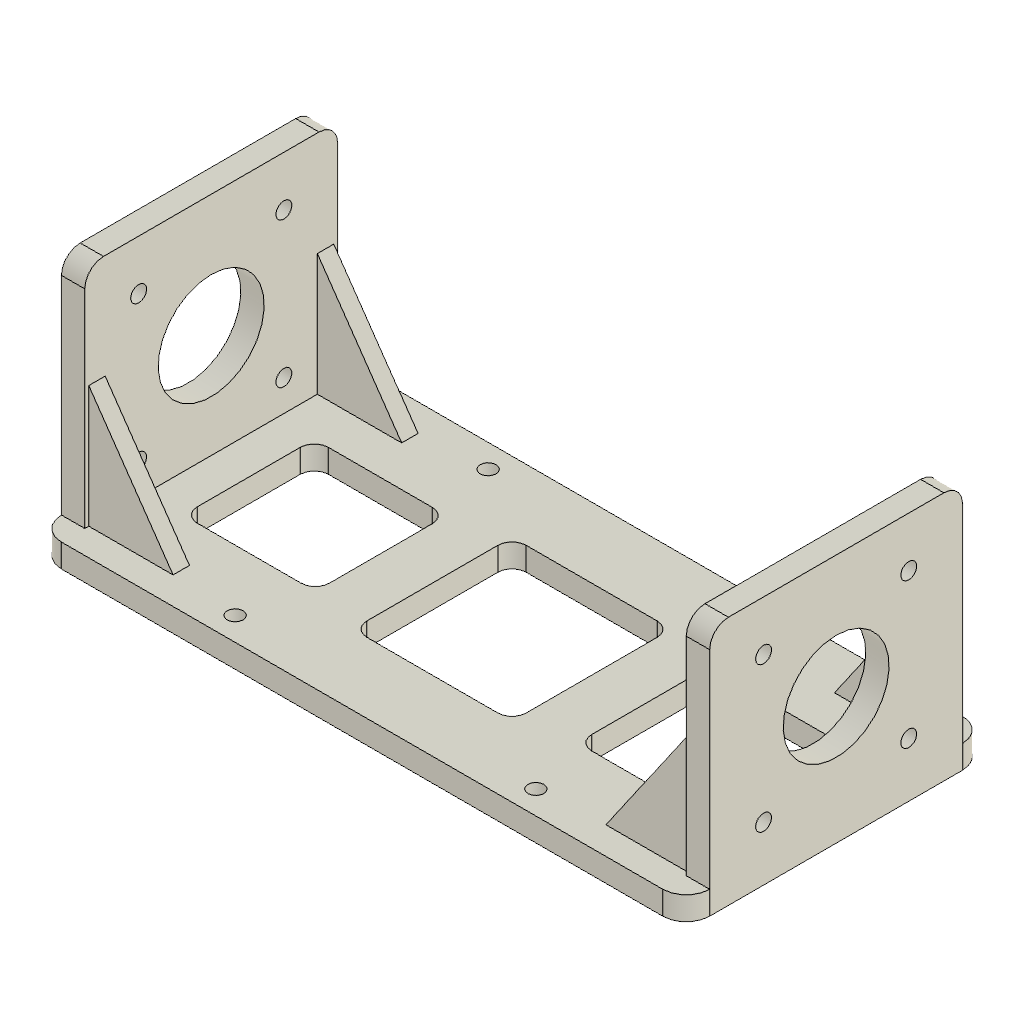
Base_NEMA17_AS5600 (Autodesk Fusion 360 design; units mm, degrees)
description: Soporte doble NEMA17 con encoders AS5600. Ejes coaxiales hacia afuera; canal abierto central. Dimensiones nominales de fijacion por confirmar.
description: Envolvente de motor + AS5600: 42.3 mm nominal y 44.2 mm confirmados. Subdivisiones, ejes, tapas y distribucion de pines son representativos.
Autodesk Fusion 360 part; units mm, degrees
sketch "Boceto1" plane through (0, 0, 0) normal (0, 0, 1) x (1, 0, 0) in component "01 Base imprimible"
  line L0 (-69.2, -32) -> (69.2, -32)
  line L1 (69.2, -32) -> (69.2, 32)
  line L2 (69.2, 32) -> (-69.2, 32)
  line L3 (-69.2, 32) -> (-69.2, -32)
  dimension "d30" = 69.2
  dimension "d31" = 32
  dimension "d32" = 138.4
  dimension "d33" = 64
  constraint horizontal L0
  constraint vertical L1
  constraint horizontal L2
  constraint vertical L3
  measures "d30" horizontal distance of origin L0.start
  measures "d31" vertical distance of origin L0.start
  measures "d32" horizontal distance of L0.start L0.end
  measures "d33" vertical distance of L0.end L1.end
extrude "01 Plataforma de 5 mm" add sketch "Boceto1" along normal blind 5 makes body 1 in component "01 Base imprimible"
fillet "02 Esquinas de plataforma R5" radius 5 4 edges at (-69.2, 32, 2.5) (69.2, 32, 2.5) (69.2, -32, 2.5) (-69.2, -32, 2.5) on bodies 1 in component "01 Base imprimible"
ref_plane "PlanoDeObra1" through (64.2, 0, 0) normal (1, 0, 0) x (0, 1, 0) in component "01 Base imprimible"
sketch "Boceto2" plane through (64.2, 0, 0) normal (1, 0, 0) x (0, 0, -1) in component "01 Base imprimible"
  line L0 (-53.3, -27) -> (-5, -27)
  line L1 (-5, -27) -> (-5, 27)
  line L2 (-5, 27) -> (-53.3, 27)
  line L3 (-53.3, 27) -> (-53.3, -27)
  dimension "d41" = 27
  dimension "d43" = 54
  constraint horizontal L0
  constraint vertical L1
  constraint horizontal L2
  constraint vertical L3
  measures "d41" vertical distance of origin L0.start
  measures "d43" vertical distance of L0.end L1.end
extrude "Placa de fijacion derecho" add sketch "Boceto2" along normal blind 5 bodies 1 in component "01 Base imprimible"
ref_plane "PlanoDeObra2" through (-64.2, 0, 0) normal (1, 0, 0) x (0, 1, 0) in component "01 Base imprimible"
sketch "Boceto3" plane through (-64.2, 0, 0) normal (1, 0, 0) x (0, 0, -1) in component "01 Base imprimible"
  line L0 (-53.3, -27) -> (-5, -27)
  line L1 (-5, -27) -> (-5, 27)
  line L2 (-5, 27) -> (-53.3, 27)
  line L3 (-53.3, 27) -> (-53.3, -27)
  dimension "d49" = 27
  dimension "d51" = 54
  constraint horizontal L0
  constraint vertical L1
  constraint horizontal L2
  constraint vertical L3
  measures "d49" vertical distance of origin L0.start
  measures "d51" vertical distance of L0.end L1.end
extrude "Placa de fijacion izquierdo" add sketch "Boceto3" against normal blind 5 bodies 1 in component "01 Base imprimible"
fillet "Esquinas superiores R4" radius 4 4 edges at (-66.7, -27, 53.3) (-66.7, 27, 53.3) (66.7, 27, 53.3) (66.7, -27, 53.3) on bodies 1 in component "01 Base imprimible"
ref_plane "PlanoDeObra3" through (64.2, 0, 0) normal (1, 0, 0) x (0, 1, 0) in component "01 Base imprimible"
sketch "Boceto4" plane through (64.2, 0, 0) normal (1, 0, 0) x (0, 0, -1) in component "01 Base imprimible"
  circle A0 centre (-27.15, 0) radius 11.3
  line L0 (0, 0) -> (-27.15, 0) construction
  circle A1 centre (-11.65, -15.5) radius 1.7
  circle A2 centre (-42.65, -15.5) radius 1.7
  circle A3 centre (-11.65, 15.5) radius 1.7
  circle A4 centre (-42.65, 15.5) radius 1.7
  dimension "d59" = 22.6
  dimension "d60" = 11.65
  dimension "d61" = 15.5
  dimension "d62" = 3.4
  dimension "d63" = 42.65
  dimension "d64" = 15.5
  dimension "d65" = 3.4
  dimension "d66" = 11.65
  dimension "d67" = 15.5
  dimension "d68" = 3.4
  dimension "d69" = 42.65
  dimension "d70" = 15.5
  dimension "d71" = 3.4
  constraint horizontal L0
  measures "d59" diameter of A0
  measures "d60" horizontal distance of L0.start A1.centre
  measures "d61" vertical distance of L0.start A1.centre
  measures "d62" diameter of A1
  measures "d63" horizontal distance of L0.start A2.centre
  measures "d64" vertical distance of L0.start A2.centre
  measures "d65" diameter of A2
  measures "d66" horizontal distance of L0.start A3.centre
  measures "d67" vertical distance of L0.start A3.centre
  measures "d68" diameter of A3
  measures "d69" horizontal distance of L0.start A4.centre
  measures "d70" vertical distance of L0.start A4.centre
  measures "d71" diameter of A4
extrude "Centrador y cuatro M3 derecho" cut sketch "Boceto4" along normal blind 5 bodies 1 in component "01 Base imprimible"
ref_plane "PlanoDeObra4" through (-64.2, 0, 0) normal (1, 0, 0) x (0, 1, 0) in component "01 Base imprimible"
sketch "Boceto5" plane through (-64.2, 0, 0) normal (1, 0, 0) x (0, 0, -1) in component "01 Base imprimible"
  circle A0 centre (-27.15, 0) radius 11.3
  line L0 (0, 0) -> (-27.15, 0) construction
  circle A1 centre (-11.65, -15.5) radius 1.7
  circle A2 centre (-42.65, -15.5) radius 1.7
  circle A3 centre (-11.65, 15.5) radius 1.7
  circle A4 centre (-42.65, 15.5) radius 1.7
  dimension "d77" = 22.6
  dimension "d78" = 11.65
  dimension "d79" = 15.5
  dimension "d80" = 3.4
  dimension "d81" = 42.65
  dimension "d82" = 15.5
  dimension "d83" = 3.4
  dimension "d84" = 11.65
  dimension "d85" = 15.5
  dimension "d86" = 3.4
  dimension "d87" = 42.65
  dimension "d88" = 15.5
  dimension "d89" = 3.4
  constraint horizontal L0
  measures "d77" diameter of A0
  measures "d78" horizontal distance of L0.start A1.centre
  measures "d79" vertical distance of L0.start A1.centre
  measures "d80" diameter of A1
  measures "d81" horizontal distance of L0.start A2.centre
  measures "d82" vertical distance of L0.start A2.centre
  measures "d83" diameter of A2
  measures "d84" horizontal distance of L0.start A3.centre
  measures "d85" vertical distance of L0.start A3.centre
  measures "d86" diameter of A3
  measures "d87" horizontal distance of L0.start A4.centre
  measures "d88" vertical distance of L0.start A4.centre
  measures "d89" diameter of A4
extrude "Centrador y cuatro M3 izquierdo" cut sketch "Boceto5" against normal blind 5 bodies 1 in component "01 Base imprimible"
ref_plane "PlanoDeObra5" through (0, 22.65, 0) normal (0, 1, 0) x (0, 0, 1) in component "01 Base imprimible"
sketch "Boceto6" plane through (0, 22.65, 0) normal (0, 1, 0) x (1, 0, 0) in component "01 Base imprimible"
  line L0 (-64.2, -5) -> (-46.2, -5)
  line L1 (-46.2, -5) -> (-64.2, -31)
  line L2 (-64.2, -31) -> (-64.2, -5)
  dimension "d94" = 64.2
  dimension "d96" = 18
  dimension "d97" = 26
  constraint horizontal L0
  constraint vertical L2
  measures "d94" horizontal distance of origin L0.start
  measures "d96" horizontal distance of L0.start L0.end
  measures "d97" vertical distance of L0.start L1.end
extrude "Refuerzo triangular -1 -1" add sketch "Boceto6" along normal blind 3.5 bodies 1 in component "01 Base imprimible"
sketch "Boceto7" plane through (0, 22.65, 0) normal (0, 1, 0) x (1, 0, 0) in component "01 Base imprimible"
  line L0 (64.2, -5) -> (46.2, -5)
  line L1 (46.2, -5) -> (64.2, -31)
  line L2 (64.2, -31) -> (64.2, -5)
  dimension "d100" = 64.2
  dimension "d102" = 18
  dimension "d103" = 26
  constraint horizontal L0
  constraint vertical L2
  measures "d100" horizontal distance of origin L0.start
  measures "d102" horizontal distance of L0.start L0.end
  measures "d103" vertical distance of L0.start L1.end
extrude "Refuerzo triangular 1 -1" add sketch "Boceto7" along normal blind 3.5 bodies 1 in component "01 Base imprimible"
ref_plane "PlanoDeObra6" through (0, -22.65, 0) normal (0, 1, 0) x (0, 0, 1) in component "01 Base imprimible"
sketch "Boceto8" plane through (0, -22.65, 0) normal (0, 1, 0) x (1, 0, 0) in component "01 Base imprimible"
  line L0 (-64.2, -5) -> (-46.2, -5)
  line L1 (-46.2, -5) -> (-64.2, -31)
  line L2 (-64.2, -31) -> (-64.2, -5)
  dimension "d108" = 64.2
  dimension "d110" = 18
  dimension "d111" = 26
  constraint horizontal L0
  constraint vertical L2
  measures "d108" horizontal distance of origin L0.start
  measures "d110" horizontal distance of L0.start L0.end
  measures "d111" vertical distance of L0.start L1.end
extrude "Refuerzo triangular -1 1" add sketch "Boceto8" against normal blind 3.5 bodies 1 in component "01 Base imprimible"
sketch "Boceto9" plane through (0, -22.65, 0) normal (0, 1, 0) x (1, 0, 0) in component "01 Base imprimible"
  line L0 (64.2, -5) -> (46.2, -5)
  line L1 (46.2, -5) -> (64.2, -31)
  line L2 (64.2, -31) -> (64.2, -5)
  dimension "d114" = 64.2
  dimension "d116" = 18
  dimension "d117" = 26
  constraint horizontal L0
  constraint vertical L2
  measures "d114" horizontal distance of origin L0.start
  measures "d116" horizontal distance of L0.start L0.end
  measures "d117" vertical distance of L0.start L1.end
extrude "Refuerzo triangular 1 1" add sketch "Boceto9" against normal blind 3.5 bodies 1 in component "01 Base imprimible"
sketch "Boceto10" plane through (0, 0, 0) normal (0, 0, 1) x (1, 0, 0) in component "01 Base imprimible"
  line L0 (-17, -17) -> (17, -17)
  line L1 (17, -17) -> (17, 17)
  line L2 (17, 17) -> (-17, 17)
  line L3 (-17, 17) -> (-17, -17)
  line L4 (-56.2, -14) -> (-28, -14)
  line L5 (-28, -14) -> (-28, 14)
  line L6 (-28, 14) -> (-56.2, 14)
  line L7 (-56.2, 14) -> (-56.2, -14)
  line L8 (28, -14) -> (56.2, -14)
  line L9 (56.2, -14) -> (56.2, 14)
  line L10 (56.2, 14) -> (28, 14)
  line L11 (28, 14) -> (28, -14)
  dimension "d120" = 17
  dimension "d121" = 17
  dimension "d122" = 34
  dimension "d123" = 34
  dimension "d124" = 56.2
  dimension "d125" = 14
  dimension "d126" = 28.2
  dimension "d127" = 28
  dimension "d128" = 28
  dimension "d129" = 14
  dimension "d130" = 28.2
  dimension "d131" = 28
  constraint horizontal L0
  constraint vertical L1
  constraint horizontal L2
  constraint vertical L3
  constraint horizontal L4
  constraint vertical L5
  constraint horizontal L6
  constraint vertical L7
  constraint horizontal L8
  constraint vertical L9
  constraint horizontal L10
  constraint vertical L11
  measures "d120" horizontal distance of origin L0.start
  measures "d121" vertical distance of origin L0.start
  measures "d122" horizontal distance of L0.start L0.end
  measures "d123" vertical distance of L0.end L1.end
  measures "d124" horizontal distance of origin L4.start
  measures "d125" vertical distance of origin L4.start
  measures "d126" horizontal distance of L4.start L4.end
  measures "d127" vertical distance of L4.end L5.end
  measures "d128" horizontal distance of origin L8.start
  measures "d129" vertical distance of origin L8.start
  measures "d130" horizontal distance of L8.start L8.end
  measures "d131" vertical distance of L8.end L9.end
extrude "Tres ventanas inferiores" cut sketch "Boceto10" along normal blind 5 bodies 1 in component "01 Base imprimible"
fillet "Ventanas R3" radius 3 12 edges at (17, 17, 2.5) (-17, 17, 2.5) (17, -17, 2.5) (-17, -17, 2.5) (-28, 14, 2.5) (-56.2, 14, 2.5) (-28, -14, 2.5) (-56.2, -14, 2.5) (56.2, 14, 2.5) (28, 14, 2.5) (56.2, -14, 2.5) (28, -14, 2.5) on bodies 1 in component "01 Base imprimible"
sketch "Boceto11" plane through (0, 0, 0) normal (0, 0, 1) x (1, 0, 0) in component "01 Base imprimible"
  circle A0 centre (-32.1, -27) radius 1.7
  dimension "d136" = 32.1
  dimension "d137" = 27
  dimension "d138" = 3.4
  measures "d136" horizontal distance of origin A0.centre
  measures "d137" vertical distance of origin A0.centre
  measures "d138" diameter of A0
extrude "Anclaje M3 -1 -1" cut sketch "Boceto11" along normal blind 5 bodies 1 in component "01 Base imprimible"
sketch "Boceto12" plane through (0, 0, 0) normal (0, 0, 1) x (1, 0, 0) in component "01 Base imprimible"
  circle A0 centre (-32.1, 27) radius 1.7
  dimension "d141" = 32.1
  dimension "d142" = 27
  dimension "d143" = 3.4
  measures "d141" horizontal distance of origin A0.centre
  measures "d142" vertical distance of origin A0.centre
  measures "d143" diameter of A0
extrude "Anclaje M3 -1 1" cut sketch "Boceto12" along normal blind 5 bodies 1 in component "01 Base imprimible"
sketch "Boceto13" plane through (0, 0, 0) normal (0, 0, 1) x (1, 0, 0) in component "01 Base imprimible"
  circle A0 centre (32.1, -27) radius 1.7
  dimension "d146" = 32.1
  dimension "d147" = 27
  dimension "d148" = 3.4
  measures "d146" horizontal distance of origin A0.centre
  measures "d147" vertical distance of origin A0.centre
  measures "d148" diameter of A0
extrude "Anclaje M3 1 -1" cut sketch "Boceto13" along normal blind 5 bodies 1 in component "01 Base imprimible"
sketch "Boceto14" plane through (0, 0, 0) normal (0, 0, 1) x (1, 0, 0) in component "01 Base imprimible"
  circle A0 centre (32.1, 27) radius 1.7
  dimension "d151" = 32.1
  dimension "d152" = 27
  dimension "d153" = 3.4
  measures "d151" horizontal distance of origin A0.centre
  measures "d152" vertical distance of origin A0.centre
  measures "d153" diameter of A0
extrude "Anclaje M3 1 1" cut sketch "Boceto14" along normal blind 5 bodies 1 in component "01 Base imprimible"
ref_plane "PlanoDeObra1" through (64.2, 0, 0) normal (1, 0, 0) x (0, 1, 0) in component "02 Referencia motor derecho - NO FABRICAR"
sketch "Boceto1 (2)" plane through (64.2, 0, 0) normal (1, 0, 0) x (0, 0, -1) in component "02 Referencia motor derecho - NO FABRICAR"
  line L0 (-48.3, -21.15) -> (-6, -21.15)
  line L1 (-6, -21.15) -> (-6, 21.15)
  line L2 (-6, 21.15) -> (-48.3, 21.15)
  line L3 (-48.3, 21.15) -> (-48.3, -21.15)
  dimension "d164" = 48.3
  dimension "d165" = 21.15
  dimension "d166" = 42.3
  dimension "d167" = 42.3
  constraint horizontal L0
  constraint horizontal L2
  constraint vertical L1
  constraint vertical L3
  measures "d164" horizontal distance of origin L0.start
  measures "d165" vertical distance of origin L0.start
  measures "d166" horizontal distance of L0.start L0.end
  measures "d167" vertical distance of L0.end L1.end
extrude "Tapa frontal" add sketch "Boceto1 (2)" against normal blind 5 separate body makes body 2 in component "02 Referencia motor derecho - NO FABRICAR"
ref_plane "PlanoDeObra2" through (59.2, 0, 0) normal (1, 0, 0) x (0, 1, 0) in component "02 Referencia motor derecho - NO FABRICAR"
sketch "Boceto2 (2)" plane through (59.2, 0, 0) normal (1, 0, 0) x (0, 0, -1) in component "02 Referencia motor derecho - NO FABRICAR"
  line L0 (-48.3, -21.15) -> (-6, -21.15)
  line L1 (-6, -21.15) -> (-6, 21.15)
  line L2 (-6, 21.15) -> (-48.3, 21.15)
  line L3 (-48.3, 21.15) -> (-48.3, -21.15)
  dimension "d172" = 48.3
  dimension "d173" = 21.15
  dimension "d174" = 42.3
  dimension "d175" = 42.3
  constraint horizontal L0
  constraint horizontal L2
  constraint vertical L1
  constraint vertical L3
  measures "d172" horizontal distance of origin L0.start
  measures "d173" vertical distance of origin L0.start
  measures "d174" horizontal distance of L0.start L0.end
  measures "d175" vertical distance of L0.end L1.end
extrude "Cuerpo del motor" add sketch "Boceto2 (2)" against normal blind 30.2 separate body makes body 3 in component "02 Referencia motor derecho - NO FABRICAR"
ref_plane "PlanoDeObra3" through (29, 0, 0) normal (1, 0, 0) x (0, 1, 0) in component "02 Referencia motor derecho - NO FABRICAR"
sketch "Boceto3 (2)" plane through (29, 0, 0) normal (1, 0, 0) x (0, 0, -1) in component "02 Referencia motor derecho - NO FABRICAR"
  line L0 (-48.3, -21.15) -> (-6, -21.15)
  line L1 (-6, -21.15) -> (-6, 21.15)
  line L2 (-6, 21.15) -> (-48.3, 21.15)
  line L3 (-48.3, 21.15) -> (-48.3, -21.15)
  dimension "d180" = 48.3
  dimension "d181" = 21.15
  dimension "d182" = 42.3
  dimension "d183" = 42.3
  constraint horizontal L0
  constraint horizontal L2
  constraint vertical L1
  constraint vertical L3
  measures "d180" horizontal distance of origin L0.start
  measures "d181" vertical distance of origin L0.start
  measures "d182" horizontal distance of L0.start L0.end
  measures "d183" vertical distance of L0.end L1.end
extrude "Tapa trasera" add sketch "Boceto3 (2)" against normal blind 5 separate body makes body 4 in component "02 Referencia motor derecho - NO FABRICAR"
ref_plane "PlanoDeObra4" through (24, 0, 0) normal (1, 0, 0) x (0, 1, 0) in component "02 Referencia motor derecho - NO FABRICAR"
sketch "Boceto4 (2)" plane through (24, 0, 0) normal (1, 0, 0) x (0, 0, -1) in component "02 Referencia motor derecho - NO FABRICAR"
  line L0 (-48.3, -21.15) -> (-6, -21.15)
  line L1 (-6, -21.15) -> (-6, 21.15)
  line L2 (-6, 21.15) -> (-48.3, 21.15)
  line L3 (-48.3, 21.15) -> (-48.3, -21.15)
  dimension "d188" = 48.3
  dimension "d189" = 21.15
  dimension "d190" = 42.3
  dimension "d191" = 42.3
  constraint horizontal L0
  constraint horizontal L2
  constraint vertical L1
  constraint vertical L3
  measures "d188" horizontal distance of origin L0.start
  measures "d189" vertical distance of origin L0.start
  measures "d190" horizontal distance of L0.start L0.end
  measures "d191" vertical distance of L0.end L1.end
extrude "Extension AS5600 - volumen representativo" add sketch "Boceto4 (2)" against normal blind 4 separate body makes body 5 in component "02 Referencia motor derecho - NO FABRICAR"
ref_plane "PlanoDeObra5" through (64.2, 0, 0) normal (1, 0, 0) x (0, 1, 0) in component "02 Referencia motor derecho - NO FABRICAR"
sketch "Boceto5 (2)" plane through (64.2, 0, 0) normal (1, 0, 0) x (0, 0, -1) in component "02 Referencia motor derecho - NO FABRICAR"
  circle A0 centre (-27.15, 0) radius 11
  line L0 (0, 0) -> (-27.15, 0) construction
  dimension "d197" = 22
  constraint horizontal L0
  measures "d197" diameter of A0
extrude "Centrador nominal (1)" add sketch "Boceto5 (2)" along normal blind 2 separate body makes body 6 in component "02 Referencia motor derecho - NO FABRICAR"
ref_plane "PlanoDeObra6" through (66.2, 0, 0) normal (1, 0, 0) x (0, 1, 0) in component "02 Referencia motor derecho - NO FABRICAR"
sketch "Boceto6 (2)" plane through (66.2, 0, 0) normal (1, 0, 0) x (0, 0, -1) in component "02 Referencia motor derecho - NO FABRICAR"
  circle A0 centre (-27.15, 0) radius 2.5
  line L0 (0, 0) -> (-27.15, 0) construction
  dimension "d203" = 5
  constraint horizontal L0
  measures "d203" diameter of A0
extrude "Eje de referencia" add sketch "Boceto6 (2)" along normal blind 22 separate body makes body 7 in component "02 Referencia motor derecho - NO FABRICAR"
ref_plane "PlanoDeObra7" through (20, 0, 0) normal (1, 0, 0) x (0, 1, 0) in component "02 Referencia motor derecho - NO FABRICAR"
sketch "Boceto7 (2)" plane through (20, 0, 0) normal (1, 0, 0) x (0, 0, -1) in component "02 Referencia motor derecho - NO FABRICAR"
  line L0 (-32.15, -5) -> (-22.15, -5)
  line L1 (-22.15, -5) -> (-22.15, 5)
  line L2 (-22.15, 5) -> (-32.15, 5)
  line L3 (-32.15, 5) -> (-32.15, -5)
  dimension "d208" = 32.15
  dimension "d209" = 5
  dimension "d210" = 10
  dimension "d211" = 10
  constraint horizontal L0
  constraint horizontal L2
  constraint vertical L1
  constraint vertical L3
  measures "d208" horizontal distance of origin L0.start
  measures "d209" vertical distance of origin L0.start
  measures "d210" horizontal distance of L0.start L0.end
  measures "d211" vertical distance of L0.end L1.end
extrude "Pines AS5600 - envolvente simplificada" add sketch "Boceto7 (2)" against normal blind 6.5 separate body makes body 8 in component "02 Referencia motor derecho - NO FABRICAR"
ref_plane "PlanoDeObra1" through (-64.2, 0, 0) normal (1, 0, 0) x (0, 1, 0) in component "02 Referencia motor izquierdo - NO FABRICAR"
sketch "Boceto1 (3)" plane through (-64.2, 0, 0) normal (1, 0, 0) x (0, 0, -1) in component "02 Referencia motor izquierdo - NO FABRICAR"
  line L0 (-48.3, -21.15) -> (-6, -21.15)
  line L1 (-6, -21.15) -> (-6, 21.15)
  line L2 (-6, 21.15) -> (-48.3, 21.15)
  line L3 (-48.3, 21.15) -> (-48.3, -21.15)
  dimension "d216" = 48.3
  dimension "d217" = 21.15
  dimension "d218" = 42.3
  dimension "d219" = 42.3
  constraint horizontal L0
  constraint horizontal L2
  constraint vertical L1
  constraint vertical L3
  measures "d216" horizontal distance of origin L0.start
  measures "d217" vertical distance of origin L0.start
  measures "d218" horizontal distance of L0.start L0.end
  measures "d219" vertical distance of L0.end L1.end
extrude "Tapa frontal'" add sketch "Boceto1 (3)" along normal blind 5 separate body makes body 9 in component "02 Referencia motor izquierdo - NO FABRICAR"
ref_plane "PlanoDeObra2" through (-59.2, 0, 0) normal (1, 0, 0) x (0, 1, 0) in component "02 Referencia motor izquierdo - NO FABRICAR"
sketch "Boceto2 (3)" plane through (-59.2, 0, 0) normal (1, 0, 0) x (0, 0, -1) in component "02 Referencia motor izquierdo - NO FABRICAR"
  line L0 (-48.3, -21.15) -> (-6, -21.15)
  line L1 (-6, -21.15) -> (-6, 21.15)
  line L2 (-6, 21.15) -> (-48.3, 21.15)
  line L3 (-48.3, 21.15) -> (-48.3, -21.15)
  dimension "d224" = 48.3
  dimension "d225" = 21.15
  dimension "d226" = 42.3
  dimension "d227" = 42.3
  constraint horizontal L0
  constraint horizontal L2
  constraint vertical L1
  constraint vertical L3
  measures "d224" horizontal distance of origin L0.start
  measures "d225" vertical distance of origin L0.start
  measures "d226" horizontal distance of L0.start L0.end
  measures "d227" vertical distance of L0.end L1.end
extrude "Cuerpo del motor'" add sketch "Boceto2 (3)" along normal blind 30.2 separate body makes body 10 in component "02 Referencia motor izquierdo - NO FABRICAR"
ref_plane "PlanoDeObra3" through (-29, 0, 0) normal (1, 0, 0) x (0, 1, 0) in component "02 Referencia motor izquierdo - NO FABRICAR"
sketch "Boceto3 (3)" plane through (-29, 0, 0) normal (1, 0, 0) x (0, 0, -1) in component "02 Referencia motor izquierdo - NO FABRICAR"
  line L0 (-48.3, -21.15) -> (-6, -21.15)
  line L1 (-6, -21.15) -> (-6, 21.15)
  line L2 (-6, 21.15) -> (-48.3, 21.15)
  line L3 (-48.3, 21.15) -> (-48.3, -21.15)
  dimension "d232" = 48.3
  dimension "d233" = 21.15
  dimension "d234" = 42.3
  dimension "d235" = 42.3
  constraint horizontal L0
  constraint horizontal L2
  constraint vertical L1
  constraint vertical L3
  measures "d232" horizontal distance of origin L0.start
  measures "d233" vertical distance of origin L0.start
  measures "d234" horizontal distance of L0.start L0.end
  measures "d235" vertical distance of L0.end L1.end
extrude "Tapa trasera'" add sketch "Boceto3 (3)" along normal blind 5 separate body makes body 11 in component "02 Referencia motor izquierdo - NO FABRICAR"
ref_plane "PlanoDeObra4" through (-24, 0, 0) normal (1, 0, 0) x (0, 1, 0) in component "02 Referencia motor izquierdo - NO FABRICAR"
sketch "Boceto4 (3)" plane through (-24, 0, 0) normal (1, 0, 0) x (0, 0, -1) in component "02 Referencia motor izquierdo - NO FABRICAR"
  line L0 (-48.3, -21.15) -> (-6, -21.15)
  line L1 (-6, -21.15) -> (-6, 21.15)
  line L2 (-6, 21.15) -> (-48.3, 21.15)
  line L3 (-48.3, 21.15) -> (-48.3, -21.15)
  dimension "d240" = 48.3
  dimension "d241" = 21.15
  dimension "d242" = 42.3
  dimension "d243" = 42.3
  constraint horizontal L0
  constraint horizontal L2
  constraint vertical L1
  constraint vertical L3
  measures "d240" horizontal distance of origin L0.start
  measures "d241" vertical distance of origin L0.start
  measures "d242" horizontal distance of L0.start L0.end
  measures "d243" vertical distance of L0.end L1.end
extrude "Extension AS5600 - volumen representativo'" add sketch "Boceto4 (3)" along normal blind 4 separate body makes body 12 in component "02 Referencia motor izquierdo - NO FABRICAR"
ref_plane "PlanoDeObra5" through (-64.2, 0, 0) normal (1, 0, 0) x (0, 1, 0) in component "02 Referencia motor izquierdo - NO FABRICAR"
sketch "Boceto5 (3)" plane through (-64.2, 0, 0) normal (1, 0, 0) x (0, 0, -1) in component "02 Referencia motor izquierdo - NO FABRICAR"
  circle A0 centre (-27.15, 0) radius 11
  line L0 (0, 0) -> (-27.15, 0) construction
  dimension "d249" = 22
  constraint horizontal L0
  measures "d249" diameter of A0
extrude "Centrador nominal (1)'" add sketch "Boceto5 (3)" against normal blind 2 separate body makes body 13 in component "02 Referencia motor izquierdo - NO FABRICAR"
ref_plane "PlanoDeObra6" through (-66.2, 0, 0) normal (1, 0, 0) x (0, 1, 0) in component "02 Referencia motor izquierdo - NO FABRICAR"
sketch "Boceto6 (3)" plane through (-66.2, 0, 0) normal (1, 0, 0) x (0, 0, -1) in component "02 Referencia motor izquierdo - NO FABRICAR"
  circle A0 centre (-27.15, 0) radius 2.5
  line L0 (0, 0) -> (-27.15, 0) construction
  dimension "d255" = 5
  constraint horizontal L0
  measures "d255" diameter of A0
extrude "Eje de referencia'" add sketch "Boceto6 (3)" against normal blind 22 separate body makes body 14 in component "02 Referencia motor izquierdo - NO FABRICAR"
ref_plane "PlanoDeObra7" through (-20, 0, 0) normal (1, 0, 0) x (0, 1, 0) in component "02 Referencia motor izquierdo - NO FABRICAR"
sketch "Boceto7 (3)" plane through (-20, 0, 0) normal (1, 0, 0) x (0, 0, -1) in component "02 Referencia motor izquierdo - NO FABRICAR"
  line L0 (-32.15, -5) -> (-22.15, -5)
  line L1 (-22.15, -5) -> (-22.15, 5)
  line L2 (-22.15, 5) -> (-32.15, 5)
  line L3 (-32.15, 5) -> (-32.15, -5)
  dimension "d260" = 32.15
  dimension "d261" = 5
  dimension "d262" = 10
  dimension "d263" = 10
  constraint horizontal L0
  constraint horizontal L2
  constraint vertical L1
  constraint vertical L3
  measures "d260" horizontal distance of origin L0.start
  measures "d261" vertical distance of origin L0.start
  measures "d262" horizontal distance of L0.start L0.end
  measures "d263" vertical distance of L0.end L1.end
extrude "Pines AS5600 - envolvente simplificada'" add sketch "Boceto7 (3)" along normal blind 6.5 separate body makes body 15 in component "02 Referencia motor izquierdo - NO FABRICAR"
component "01 Base imprimible" placed x (1, 0, 0) y (0, 1, 0) z (0, 0, 1) at (0, 0, 0)
component "02 Referencia motor derecho - NO FABRICAR" placed x (1, 0, 0) y (0, 1, 0) z (0, 0, 1) at (0, 0, 0)
component "02 Referencia motor izquierdo - NO FABRICAR" placed x (1, 0, 0) y (0, 1, 0) z (0, 0, 1) at (0, 0, 0)
equation "motor_ancho = 42.3 mm" comment "Envolvente NEMA17 supuesta; verificar con calibre."
equation "motor_largo = 44.2 mm" comment "Medido por usuario: motor y extension AS5600, sin pines."
equation "pines_salida = 6.5 mm" comment "Medido por usuario: saliente de pines desde extension."
equation "cable_reserva = 18 mm" comment "Espacio total tras cada encoder solicitado por usuario, incluye pines."
equation "separacion_extra = 4 mm" comment "Margen central entre las dos reservas de cable."
equation "canal_central = 2 * cable_reserva + separacion_extra" comment "Separacion libre entre caras traseras de encoders."
equation "largo_interior = 2 * motor_largo + canal_central" comment "Entre caras interiores de las placas de fijacion."
equation "espesor_base = 5 mm" comment "Espesor de plataforma para prototipo impreso."
equation "espesor_soporte = 5 mm" comment "Espesor de cada placa frontal de motor."
equation "largo_total = largo_interior + 2 * espesor_soporte" comment "Dimension transversal exterior de la base."
equation "fondo_base = 64 mm" comment "Dimension longitudinal de la base."
equation "ancho_soporte = 54 mm" comment "Anchura de las placas de fijacion."
equation "holgura_inferior = 1 mm" comment "Holgura entre carcasa del motor y plataforma."
equation "eje_altura = espesor_base + holgura_inferior + motor_ancho / 2" comment "Altura del eje respecto a cara inferior de base."
equation "alto_soporte = espesor_base + holgura_inferior + motor_ancho + 5 mm" comment "Altura total de placas."
equation "paso_NEMA = 31 mm" comment "Patron nominal cuadrado NEMA17: confirmar con motor real."
equation "diam_M3 = 3.4 mm" comment "Paso libre para tornillos M3; ajustar a impresora."
equation "diam_centrador = 22.6 mm" comment "Alojamiento de resalte nominal de 22 mm; confirmar motor real."
equation "nervio_espesor = 3.5 mm" comment "Espesor de cuatro cartelas."
equation "nervio_largo = 18 mm" comment "Longitud interior de cartelas."
equation "nervio_alto = 26 mm" comment "Altura de cartelas desde plataforma."
equation "nervio_holgura = 1.5 mm" comment "Separacion lateral entre motor y cartelas."
equation "radio_exterior = 5 mm" comment "Radio de esquinas exteriores de plataforma."
equation "radio_superior = 4 mm" comment "Radio superior de placas de fijacion."
equation "radio_ventanas = 3 mm" comment "Radio en esquinas de ventanas de plataforma."
equation "ventana_cable_ancho = canal_central - 6 mm" comment "Ventana inferior bajo la zona de encoders."
equation "ventana_cable_fondo = 34 mm" comment "Ventana de cableado, longitudinal."
equation "ventana_motor_ancho = motor_largo - 16 mm" comment "Ventanas de ventilacion bajo los motores."
equation "ventana_motor_fondo = 28 mm" comment "Anchura longitudinal de ventilacion."
equation "d30 = -( -largo_total / 2 )"
equation "d31 = -( -fondo_base / 2 )"
equation "d32 = ( largo_total / 2 ) - ( -largo_total / 2 )"
equation "d33 = ( fondo_base / 2 ) - ( -fondo_base / 2 )"
equation "d34 = espesor_base"
equation "d37 = radio_exterior"
equation "d38 = largo_interior / 2"
equation "d40 = -( -( alto_soporte ) )"
equation "d41 = -( ( -ancho_soporte / 2 ) )"
equation "d42 = ( -( espesor_base ) ) - ( -( alto_soporte ) )"
equation "d43 = ( ( ancho_soporte / 2 ) ) - ( ( -ancho_soporte / 2 ) )"
equation "d44 = espesor_soporte"
equation "d46 = -largo_interior / 2"
equation "d48 = -( -( alto_soporte ) )"
equation "d49 = -( ( -ancho_soporte / 2 ) )"
equation "d50 = ( -( espesor_base ) ) - ( -( alto_soporte ) )"
equation "d51 = ( ( ancho_soporte / 2 ) ) - ( ( -ancho_soporte / 2 ) )"
equation "d52 = -( -( -espesor_soporte ) )"
equation "d55 = radio_superior"
equation "d56 = largo_interior / 2"
equation "d58 = -( -( eje_altura ) )"
equation "d59 = diam_centrador"
equation "d60 = -( -( eje_altura - paso_NEMA / 2 ) )"
equation "d61 = -( ( -paso_NEMA / 2 ) )"
equation "d62 = diam_M3"
equation "d63 = -( -( eje_altura + paso_NEMA / 2 ) )"
equation "d64 = -( ( -paso_NEMA / 2 ) )"
equation "d65 = diam_M3"
equation "d66 = -( -( eje_altura - paso_NEMA / 2 ) )"
equation "d67 = ( paso_NEMA / 2 )"
equation "d68 = diam_M3"
equation "d69 = -( -( eje_altura + paso_NEMA / 2 ) )"
equation "d70 = ( paso_NEMA / 2 )"
equation "d71 = diam_M3"
equation "d72 = espesor_soporte"
equation "d74 = -largo_interior / 2"
equation "d76 = -( -( eje_altura ) )"
equation "d77 = diam_centrador"
equation "d78 = -( -( eje_altura - paso_NEMA / 2 ) )"
equation "d79 = -( ( -paso_NEMA / 2 ) )"
equation "d80 = diam_M3"
equation "d81 = -( -( eje_altura + paso_NEMA / 2 ) )"
equation "d82 = -( ( -paso_NEMA / 2 ) )"
equation "d83 = diam_M3"
equation "d84 = -( -( eje_altura - paso_NEMA / 2 ) )"
equation "d85 = ( paso_NEMA / 2 )"
equation "d86 = diam_M3"
equation "d87 = -( -( eje_altura + paso_NEMA / 2 ) )"
equation "d88 = ( paso_NEMA / 2 )"
equation "d89 = diam_M3"
equation "d90 = -( -( -espesor_soporte ) )"
equation "d92 = -( -( motor_ancho / 2 + nervio_holgura ) )"
equation "d94 = -( ( -largo_interior / 2 ) )"
equation "d95 = -( -( espesor_base ) )"
equation "d96 = nervio_largo"
equation "d97 = nervio_alto"
equation "d98 = nervio_espesor"
equation "d100 = ( largo_interior / 2 )"
equation "d101 = -( -( espesor_base ) )"
equation "d102 = nervio_largo"
equation "d103 = nervio_alto"
equation "d104 = nervio_espesor"
equation "d106 = -( ( motor_ancho / 2 + nervio_holgura ) )"
equation "d108 = -( ( -largo_interior / 2 ) )"
equation "d109 = -( -( espesor_base ) )"
equation "d110 = nervio_largo"
equation "d111 = nervio_alto"
equation "d112 = -( -( -nervio_espesor ) )"
equation "d114 = ( largo_interior / 2 )"
equation "d115 = -( -( espesor_base ) )"
equation "d116 = nervio_largo"
equation "d117 = nervio_alto"
equation "d118 = -( -( -nervio_espesor ) )"
equation "d120 = -( -ventana_cable_ancho / 2 )"
equation "d121 = -( -ventana_cable_fondo / 2 )"
equation "d122 = ( ventana_cable_ancho / 2 ) - ( -ventana_cable_ancho / 2 )"
equation "d123 = ( ventana_cable_fondo / 2 ) - ( -ventana_cable_fondo / 2 )"
equation "d124 = -( -( canal_central / 2 + motor_largo / 2 ) - ventana_motor_ancho / 2 )"
equation "d125 = -( -ventana_motor_fondo / 2 )"
equation "d126 = ( -( canal_central / 2 + motor_largo / 2 ) + ventana_motor_ancho / 2 ) - ( -( canal_central / 2 + motor_largo / 2 ) - ventana_motor_ancho / 2 )"
equation "d127 = ( ventana_motor_fondo / 2 ) - ( -ventana_motor_fondo / 2 )"
equation "d128 = ( canal_central / 2 + motor_largo / 2 ) - ventana_motor_ancho / 2"
equation "d129 = -( -ventana_motor_fondo / 2 )"
equation "d130 = ( ( canal_central / 2 + motor_largo / 2 ) + ventana_motor_ancho / 2 ) - ( ( canal_central / 2 + motor_largo / 2 ) - ventana_motor_ancho / 2 )"
equation "d131 = ( ventana_motor_fondo / 2 ) - ( -ventana_motor_fondo / 2 )"
equation "d132 = espesor_base"
equation "d135 = radio_ventanas"
equation "d136 = -( -largo_interior / 4 )"
equation "d137 = -( -( fondo_base / 2 - 5 mm ) )"
equation "d138 = diam_M3"
equation "d139 = espesor_base"
equation "d141 = -( -largo_interior / 4 )"
equation "d142 = ( fondo_base / 2 - 5 mm )"
equation "d143 = diam_M3"
equation "d144 = espesor_base"
equation "d146 = largo_interior / 4"
equation "d147 = -( -( fondo_base / 2 - 5 mm ) )"
equation "d148 = diam_M3"
equation "d149 = espesor_base"
equation "d151 = largo_interior / 4"
equation "d152 = ( fondo_base / 2 - 5 mm )"
equation "d153 = diam_M3"
equation "d154 = espesor_base"
equation "ref_extension = 4 mm" comment "SOLO VISUAL: division aproximada entre motor y soporte rojo; largo total 44.2 mm si confirmado."
equation "ref_tapa = 5 mm" comment "SOLO VISUAL: espesor aproximado de las tapas metalicas."
equation "ref_eje_largo = 24 mm" comment "SOLO VISUAL: longitud de eje no medida."
equation "ref_eje_diam = 5 mm" comment "SOLO VISUAL: diametro de eje supuesto."
equation "ref_centrador_diam = 22 mm" comment "SOLO VISUAL: centrador nominal NEMA17."
equation "ref_centrador_alto = 2 mm" comment "SOLO VISUAL: alto nominal de resalte frontal."
equation "d162 = largo_interior / 2"
equation "d164 = -( -( eje_altura + motor_ancho / 2 ) )"
equation "d165 = -( ( -motor_ancho / 2 ) )"
equation "d166 = ( -( eje_altura - motor_ancho / 2 ) ) - ( -( eje_altura + motor_ancho / 2 ) )"
equation "d167 = ( ( motor_ancho / 2 ) ) - ( ( -motor_ancho / 2 ) )"
equation "d168 = -( -( -ref_tapa ) )"
equation "d170 = largo_interior / 2 - ref_tapa"
equation "d172 = -( -( eje_altura + motor_ancho / 2 ) )"
equation "d173 = -( ( -motor_ancho / 2 ) )"
equation "d174 = ( -( eje_altura - motor_ancho / 2 ) ) - ( -( eje_altura + motor_ancho / 2 ) )"
equation "d175 = ( ( motor_ancho / 2 ) ) - ( ( -motor_ancho / 2 ) )"
equation "d176 = -( -( -( motor_largo - ref_extension - 2 * ref_tapa ) ) )"
equation "d178 = canal_central / 2 + ( ref_extension + ref_tapa )"
equation "d180 = -( -( eje_altura + motor_ancho / 2 ) )"
equation "d181 = -( ( -motor_ancho / 2 ) )"
equation "d182 = ( -( eje_altura - motor_ancho / 2 ) ) - ( -( eje_altura + motor_ancho / 2 ) )"
equation "d183 = ( ( motor_ancho / 2 ) ) - ( ( -motor_ancho / 2 ) )"
equation "d184 = -( -( -ref_tapa ) )"
equation "d186 = canal_central / 2 + ref_extension"
equation "d188 = -( -( eje_altura + motor_ancho / 2 ) )"
equation "d189 = -( ( -motor_ancho / 2 ) )"
equation "d190 = ( -( eje_altura - motor_ancho / 2 ) ) - ( -( eje_altura + motor_ancho / 2 ) )"
equation "d191 = ( ( motor_ancho / 2 ) ) - ( ( -motor_ancho / 2 ) )"
equation "d192 = -( -( -ref_extension ) )"
equation "d194 = largo_interior / 2"
equation "d196 = -( -( eje_altura ) )"
equation "d197 = ref_centrador_diam"
equation "d198 = ref_centrador_alto"
equation "d200 = largo_interior / 2 + ref_centrador_alto"
equation "d202 = -( -( eje_altura ) )"
equation "d203 = ref_eje_diam"
equation "d204 = ( ref_eje_largo - ref_centrador_alto )"
equation "d206 = canal_central / 2"
equation "d208 = -( -( eje_altura + 5 mm ) )"
equation "d209 = -( ( -5 mm ) )"
equation "d210 = ( -( eje_altura - 5 mm ) ) - ( -( eje_altura + 5 mm ) )"
equation "d211 = ( ( 5 mm ) ) - ( ( -5 mm ) )"
equation "d212 = -( -( -pines_salida ) )"
equation "d214 = -largo_interior / 2"
equation "d216 = -( -( eje_altura + motor_ancho / 2 ) )"
equation "d217 = -( ( -motor_ancho / 2 ) )"
equation "d218 = ( -( eje_altura - motor_ancho / 2 ) ) - ( -( eje_altura + motor_ancho / 2 ) )"
equation "d219 = ( ( motor_ancho / 2 ) ) - ( ( -motor_ancho / 2 ) )"
equation "d220 = ref_tapa"
equation "d222 = -largo_interior / 2 + ref_tapa"
equation "d224 = -( -( eje_altura + motor_ancho / 2 ) )"
equation "d225 = -( ( -motor_ancho / 2 ) )"
equation "d226 = ( -( eje_altura - motor_ancho / 2 ) ) - ( -( eje_altura + motor_ancho / 2 ) )"
equation "d227 = ( ( motor_ancho / 2 ) ) - ( ( -motor_ancho / 2 ) )"
equation "d228 = ( motor_largo - ref_extension - 2 * ref_tapa )"
equation "d230 = -canal_central / 2 - ( ref_extension + ref_tapa )"
equation "d232 = -( -( eje_altura + motor_ancho / 2 ) )"
equation "d233 = -( ( -motor_ancho / 2 ) )"
equation "d234 = ( -( eje_altura - motor_ancho / 2 ) ) - ( -( eje_altura + motor_ancho / 2 ) )"
equation "d235 = ( ( motor_ancho / 2 ) ) - ( ( -motor_ancho / 2 ) )"
equation "d236 = ref_tapa"
equation "d238 = -canal_central / 2 - ref_extension"
equation "d240 = -( -( eje_altura + motor_ancho / 2 ) )"
equation "d241 = -( ( -motor_ancho / 2 ) )"
equation "d242 = ( -( eje_altura - motor_ancho / 2 ) ) - ( -( eje_altura + motor_ancho / 2 ) )"
equation "d243 = ( ( motor_ancho / 2 ) ) - ( ( -motor_ancho / 2 ) )"
equation "d244 = ref_extension"
equation "d246 = -largo_interior / 2"
equation "d248 = -( -( eje_altura ) )"
equation "d249 = ref_centrador_diam"
equation "d250 = -( -( -ref_centrador_alto ) )"
equation "d252 = -largo_interior / 2 - ref_centrador_alto"
equation "d254 = -( -( eje_altura ) )"
equation "d255 = ref_eje_diam"
equation "d256 = -( -( -( ref_eje_largo - ref_centrador_alto ) ) )"
equation "d258 = -canal_central / 2"
equation "d260 = -( -( eje_altura + 5 mm ) )"
equation "d261 = -( ( -5 mm ) )"
equation "d262 = ( -( eje_altura - 5 mm ) ) - ( -( eje_altura + 5 mm ) )"
equation "d263 = ( ( 5 mm ) ) - ( ( -5 mm ) )"
equation "d264 = pines_salida"
named bodies: "Base NEMA17 - pieza unica", "Tapa frontal", "Cuerpo del motor", "Tapa trasera", "Extension AS5600 - volumen representativo"
